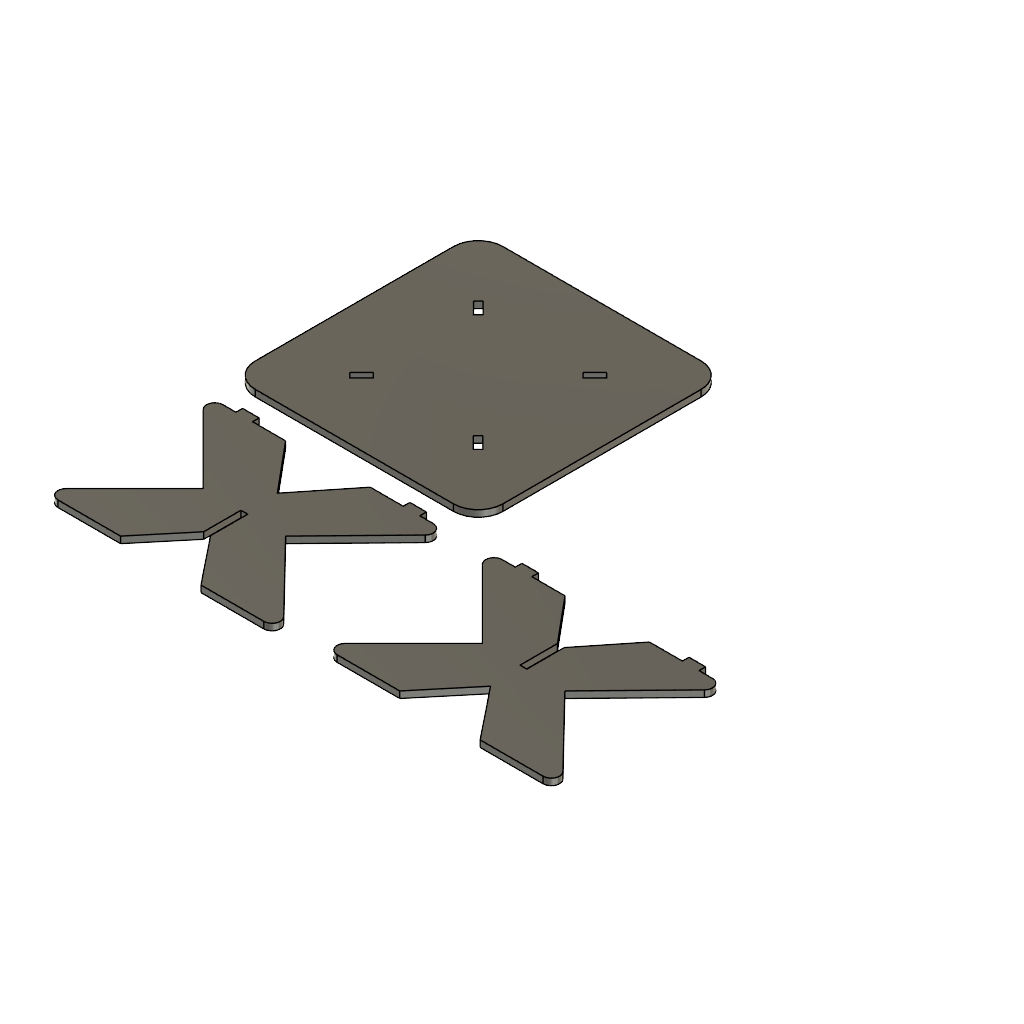
mesa-midterm (Autodesk Fusion 360 design; units mm, degrees)
part number: 2026-11-18-09-30-01-636
Autodesk Fusion 360 part; units mm, degrees
sketch "Boceto1" plane through (0, 0, 0) normal (0, 0, 1) x (1, 0, 0)
  line L0 (15, 0) -> (135, 0)
  line L1 (150, 15) -> (150, 135)
  line L2 (135, 150) -> (15, 150)
  line L3 (0, 135) -> (0, 15)
  arc A0 (15, 150) -> (0, 135) centre (15, 135) ccw
  arc A1 (150, 135) -> (135, 150) centre (135, 135) ccw
  arc A2 (0, 15) -> (15, 0) centre (15, 15) ccw
  arc A3 (135, 0) -> (150, 15) centre (135, 15) ccw
  line L4 (51.1197, -67.7446) -> (9.6552, -109.2091)
  line L5 (101.1197, -67.7446) -> (142.8359, -110.5846)
  line L6 (51.1197, -117.7446) -> (74.0197, -90.2646)
  line L7 (13.1907, -117.7446) -> (51.1197, -117.7446)
  line L8 (101.1197, -119.0728) -> (78.1197, -90.2509)
  line L9 (139.2537, -119.0728) -> (101.1197, -119.0728)
  line L10 (101.0197, -16.4165) -> (76.0773, -47.6938)
  line L11 (101.1197, -67.7446) -> (142.8359, -24.9047)
  line L12 (51.1197, -67.7446) -> (9.6552, -26.2802)
  line L13 (51.1197, -17.7446) -> (76.0773, -47.6938)
  arc A4 (9.6552, -109.2091) -> (13.1907, -117.7446) centre (13.1907, -112.7446) ccw
  arc A5 (139.2537, -119.0728) -> (142.8359, -110.5846) centre (139.2537, -114.0728) ccw
  arc A6 (13.1907, -17.7446) -> (9.6552, -26.2802) centre (13.1907, -22.7446) ccw
  arc A7 (142.8359, -24.9047) -> (139.2537, -16.4165) centre (139.2537, -21.4165) ccw
  line L14 (305.0234, -115.7385) -> (266.8894, -115.7385)
  line L15 (178.9605, -114.4103) -> (216.8894, -114.4103)
  arc A8 (178.9605, -14.4103) -> (175.4249, -22.9459) centre (178.9605, -19.4103) ccw
  line L16 (216.8894, -114.4103) -> (241.8894, -84.4103)
  line L17 (216.8894, -64.4103) -> (175.4249, -22.9459)
  line L18 (266.8894, -64.4103) -> (308.6056, -21.5704)
  line L19 (266.7894, -13.0822) -> (243.8894, -41.8182)
  arc A9 (175.4249, -105.8748) -> (178.9605, -114.4103) centre (178.9605, -109.4103) ccw
  line L20 (266.8894, -64.4103) -> (308.6056, -107.2503)
  arc A10 (305.0234, -115.7385) -> (308.6056, -107.2503) centre (305.0234, -110.7385) ccw
  line L21 (266.8894, -115.7385) -> (241.8894, -84.4103)
  line L22 (216.9894, -14.4104) -> (239.7894, -41.7593)
  line L23 (216.8894, -64.4103) -> (175.4249, -105.8748)
  arc A11 (308.6056, -21.5704) -> (305.0234, -13.0821) centre (305.0234, -18.0821) ccw
  line L24 (239.7894, -64.4103) -> (239.7894, -41.7593)
  line L25 (243.8894, -64.4103) -> (243.8894, -41.8182)
  line L26 (239.7894, -64.4103) -> (243.8894, -64.4103)
  line L27 (74.0197, -67.7446) -> (74.0197, -90.2646)
  line L28 (78.1197, -67.7446) -> (78.1197, -90.2509)
  line L29 (74.0197, -67.7446) -> (78.1197, -67.7446)
  line L30 (51.1197, -17.7446) -> (31.1197, -17.7446)
  line L31 (31.1197, -17.7446) -> (31.1197, -13.7446)
  line L32 (31.1197, -13.7446) -> (21.0197, -13.7446)
  line L33 (21.0197, -13.7446) -> (21.0197, -17.7446)
  line L34 (21.0197, -17.7446) -> (13.1907, -17.7446)
  line L35 (101.0197, -16.4165) -> (121.0197, -16.4165)
  line L36 (121.0197, -16.4165) -> (121.0197, -12.4165)
  line L37 (121.0197, -12.4165) -> (131.1197, -12.4165)
  line L38 (131.1197, -12.4165) -> (131.1197, -16.4165)
  line L39 (139.2537, -16.4165) -> (131.1197, -16.4165)
  line L40 (216.9894, -14.4104) -> (196.9894, -14.4104)
  line L41 (196.9894, -14.4104) -> (196.9894, -10.4104)
  line L42 (196.9894, -10.4104) -> (186.8894, -10.4104)
  line L43 (186.8894, -10.4104) -> (186.8894, -14.4104)
  line L44 (178.9605, -14.4103) -> (186.8894, -14.4104)
  line L45 (266.7894, -13.0822) -> (286.7894, -13.0822)
  line L46 (286.7894, -13.0822) -> (286.7894, -9.0822)
  line L47 (286.7894, -9.0822) -> (296.8894, -9.0822)
  line L48 (296.8894, -9.0822) -> (296.8894, -13.0822)
  line L49 (296.8894, -13.0822) -> (305.0234, -13.0821)
  line L50 (105.3349, 108.1633) -> (112.4767, 115.3051)
  line L51 (112.4767, 115.3051) -> (115.3758, 112.4059)
  line L52 (115.3758, 112.4059) -> (108.234, 105.2642)
  line L53 (41.8367, 105.3349) -> (34.6949, 112.4767)
  line L54 (34.6949, 112.4767) -> (37.5941, 115.3758)
  line L55 (37.5941, 115.3758) -> (44.7358, 108.234)
  line L56 (41.8367, 44.6651) -> (34.6949, 37.5233)
  line L57 (34.6949, 37.5233) -> (37.5941, 34.6242)
  line L58 (37.5941, 34.6242) -> (44.7358, 41.766)
  line L59 (108.1633, 44.6651) -> (115.3051, 37.5233)
  line L60 (115.3051, 37.5233) -> (112.4059, 34.6242)
  line L61 (112.4059, 34.6242) -> (105.2642, 41.766)
  line L62 (105.2642, 41.766) -> (108.1633, 44.6651)
  line L63 (41.8367, 44.6651) -> (44.7358, 41.766)
  line L64 (41.8367, 105.3349) -> (44.7358, 108.234)
  line L65 (105.3349, 108.1633) -> (108.234, 105.2642)
  point P0 (150, 0)
  point P1 (0, 150)
  dimension "d1" = 150
  dimension "d2" = 150
  dimension "d3" = 15
  dimension "d4" = 15
  dimension "d5" = 15
  dimension "d6" = 15
  dimension "d20" = 5
  dimension "d21" = 5
  dimension "d22" = 5
  dimension "d23" = 5
  dimension "d24" = 5
  dimension "d25" = 5
  dimension "d26" = 5
  dimension "d27" = 5
  dimension "d34" = 4.1
  dimension "d35" = 4.1
  dimension "d38" = 20
  dimension "d39" = 4
  dimension "d40" = 10.1
  dimension "d41" = 4
  dimension "d42" = 20
  dimension "d43" = 4
  dimension "d44" = 10.1
  dimension "d45" = 4
  dimension "d46" = 20
  dimension "d47" = 4
  dimension "d48" = 10.1
  dimension "d49" = 4
  dimension "d50" = 20
  dimension "d51" = 4
  dimension "d52" = 10.1
  dimension "d53" = 4
  dimension "d57" = 10.1
  dimension "d58" = 4.1
  dimension "d64" = 10.1
  dimension "d65" = 4.1
  dimension "d68" = 10.1
  dimension "d69" = 4.1
  dimension "d72" = 10.1
  dimension "d73" = 4.1
  constraint horizontal L0
  constraint vertical L1
  constraint horizontal L2
  constraint vertical L3
  constraint coincident P1 L2
  constraint coincident P1 L3
  constraint tangent L2 A0
  constraint tangent L3 A0
  constraint tangent L2 A1
  constraint tangent L1 A1
  constraint coincident origin L3
  constraint coincident origin L0
  constraint tangent L3 A2
  constraint tangent L0 A2
  constraint coincident P0 L0
  constraint coincident P0 L1
  constraint tangent L0 A3
  constraint tangent L1 A3
  constraint perpendicular L1 L7
  constraint horizontal L9
  constraint tangent L7 A4
  constraint tangent L4 A4
  constraint tangent L5 A5
  constraint tangent L9 A5
  constraint tangent L12 A6
  constraint tangent L11 A7
  constraint horizontal L14
  constraint tangent L15 A9
  constraint tangent A9 L23
  constraint tangent L20 A10
  constraint tangent L14 A10
  constraint tangent A8 L17
  constraint tangent L18 A11
  constraint perpendicular L25 L26
  constraint perpendicular L28 L29
  constraint perpendicular L30 L31
  constraint perpendicular L31 L32
  constraint perpendicular L32 L33
  constraint tangent A6 L34
  constraint horizontal L35
  constraint perpendicular L35 L36
  constraint perpendicular L36 L37
  constraint perpendicular L37 L38
  constraint tangent A7 L39
  constraint horizontal L40
  constraint perpendicular L40 L41
  constraint perpendicular L41 L42
  constraint perpendicular L42 L43
  constraint tangent A8 L44
  constraint perpendicular L43 L45
  constraint perpendicular L45 L46
  constraint perpendicular L46 L47
  constraint perpendicular L47 L48
  constraint tangent A11 L49
  constraint perpendicular L50 L51
  constraint perpendicular L53 L54
  constraint perpendicular L56 L57
  constraint perpendicular L59 L60
  constraint perpendicular L59 L62
  constraint perpendicular L58 L63
  constraint perpendicular L55 L64
  constraint perpendicular L52 L65
  measures "d1" distance of origin P0
  measures "d2" distance of origin P1
  measures "d3" radius of A0
  measures "d4" radius of A1
  measures "d5" radius of A2
  measures "d6" radius of A3
  measures "d20" radius of A4
  measures "d21" radius of A5
  measures "d22" radius of A6
  measures "d23" radius of A7
  measures "d24" radius of A9
  measures "d25" radius of A10
  measures "d26" radius of A8
  measures "d27" radius of A11
  measures "d34" distance of L25.start L24.start
  measures "d35" distance of L28.start L27.start
  measures "d38" distance of L13.start L30.end
  measures "d39" distance of L30.end L31.end
  measures "d40" distance of L31.end L32.end
  measures "d41" distance of L32.end L33.end
  measures "d42" distance of L10.start L35.end
  measures "d43" distance of L35.end L36.end
  measures "d44" distance of L36.end L37.end
  measures "d45" distance of L37.end L38.end
  measures "d46" distance of L22.start L40.end
  measures "d47" distance of L40.end L41.end
  measures "d48" distance of L41.end L42.end
  measures "d49" distance of L42.end L43.end
  measures "d50" distance of L19.start L45.end
  measures "d51" distance of L45.end L46.end
  measures "d52" distance of L46.end L47.end
  measures "d53" distance of L47.end L48.end
  measures "d57" distance of L50.start L50.end
  measures "d58" distance of L50.end L51.end
  measures "d64" distance of L53.start L53.end
  measures "d65" distance of L53.end L54.end
  measures "d68" distance of L56.start L56.end
  measures "d69" distance of L56.end L57.end
  measures "d72" distance of L59.start L59.end
  measures "d73" distance of L59.end L60.end
extrude "Extruir1" add sketch "Boceto1" along normal blind 4 makes body 1 at (85.1116, 86.0544, 0) makes body 2 at (115.0251, -99.134, 0) makes body 3 at (280.7948, -95.7997, 0)
equation "d34 = 4.00 mm + 2 * keff"
equation "d35 = 4.00 mm + 2 * keff"
equation "keff = 0.05 mm"
equation "d40 = 10 mm + 2 * keff"
equation "d44 = 10 mm + 2 * keff"
equation "d48 = 10 mm + 2 * keff"
equation "d52 = 10 mm + 2 * keff"
equation "d57 = 10 mm + 2 * keff"
equation "d58 = 4 mm + 2 * keff"
equation "d64 = 10 mm + 2 * keff"
equation "d65 = 4 mm + 2 * keff"
equation "d68 = 10 mm + 2 * keff"
equation "d69 = 4 mm + 2 * keff"
equation "d72 = 10 mm + 2 * keff"
equation "d73 = 4 mm + 2 * keff"
